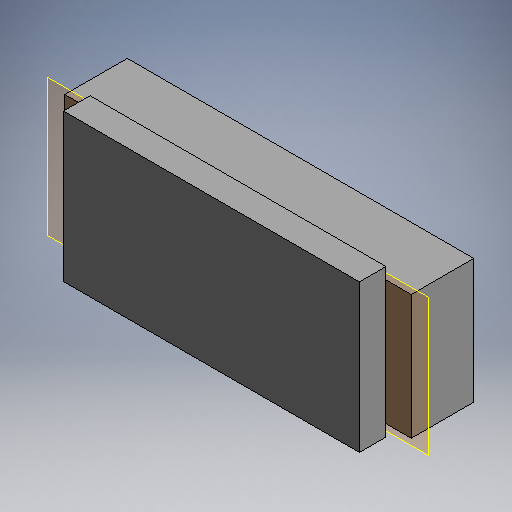
# Autodesk Inventor part: Junction_Box_Positive
Saved by Autodesk Inventor 2026.2 (Build 302298000, 298)
## iProperties
Part Number: Junction_Box_Positive
Material: Generic
Document SubType Name: Modeling
Designer: Jacob
Appearance: Default
Author: Jacob
Autodesk Inventor part; units mm, degrees
ref_plane "YZ Plane" through (0, 0, 0) normal (1, 0, 0) x (0, 1, 0)
ref_plane "XZ Plane" through (0, 0, 0) normal (0, 1, 0) x (-1, 0, 0)
sketch "Sketch1" plane through (0, 0, 0) normal (0, 0, 1) x (1, 0, 0)
  line L0 (-33.25, -11.95) -> (33.25, -11.95)
  line L1 (33.25, -11.95) -> (33.25, 11.95)
  line L2 (33.25, 11.95) -> (-33.25, 11.95)
  line L3 (-33.25, 11.95) -> (-33.25, -11.95)
  constraints: 8 end point, 2 parallel, 1 horizontal, 1 perpendicular
extrude "Extrusion1" add sketch "Sketch1" along normal blind 12
ref_plane "Work Plane1" through (0, 0, 12) normal (0, 0, 1) x (1, 0, 0)
sketch "Sketch2" plane through (0, 0, 12) normal (0, 0, 1) x (1, 0, 0)
  line L0 (-28.4, -14.175) -> (28.4, -14.175)
  line L1 (28.4, -14.175) -> (28.4, 14.175)
  line L2 (28.4, 14.175) -> (-28.4, 14.175)
  line L3 (-28.4, 14.175) -> (-28.4, -14.175)
  constraints: 8 end point, 2 parallel, 1 horizontal, 1 perpendicular
extrude "Extrusion2" add sketch "Sketch2" along normal blind 5.1
body "Solid1"
